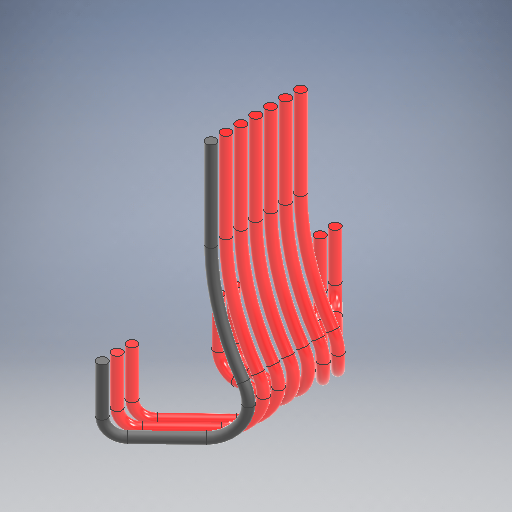
# Autodesk Inventor part: Charging Cables
Saved by Autodesk Inventor 2025 (Build 290162010, 162A)
## iProperties
Created: 2025-08-20
Part Number: Charging Cables
Material: Generic
Document SubType Name: Modeling
Designer: Glen Collingwood
Density: 1 g/cm^3
Appearance: Default
Author: Glen Collingwood
Autodesk Inventor part; units mm, degrees
sketch "Sketch1" plane through (0, 0, 0) normal (0, 1, 0) x (-1, 0, 0)
  circle A0 centre (0, 0) radius 0.85
  dimension "d0" = 1.7
  constraints: 1 centre point, 1 coincident
  measures "d0" diameter of A0
extrude "Extrusion1" add sketch "Sketch1" against normal blind 15
pattern_linear "Rectangular Pattern1" count 7 spacing 2.5 along (0, 0, 1) of "Extrusion1" first direction both ways yes
sketch "Sketch2" plane through (0, 0, 0) normal (0, 0, 1) x (1, 0, 0)
  line L0 (-14, -40) -> (22, -40) construction
  line L1 (-0.85, -15) -> (0.85, -15) projected
  arc A0 (0, -15) -> (5.3804, -32.1429) centre (30, -15) ccw
  arc A1 (6.2772, -35) -> (5.3804, -32.1429) centre (1.2772, -35) ccw
  line L2 (1.2772, -35) -> (6.2772, -35) construction
  point P0 (0, 0)
  dimension "d6" = 25
  dimension "d7" = 60
  dimension "d8" = 10
  constraints: 4 end point, 4 point on circle, 2 centre point, 2 horizontal, 2 midpoint, 2 tangent, 1 horizontal alignment
  measures "d6" distance between parallel lines of L0 L1
  measures "d7" diameter of A0
  measures "d8" diameter of A1
sketch "Sketch3" plane through (0, -15, 0) normal (0, -1, 0) x (1, 0, 0)
  circle A0 centre (0, 0) radius 0.85 projected
  circle A1 centre (0, -7.5) radius 0.85 projected
  circle A2 centre (0, -5) radius 0.85 projected
  circle A3 centre (0, -2.5) radius 0.85 projected
  circle A4 centre (0, 2.5) radius 0.85 projected
  circle A5 centre (0, 5) radius 0.85 projected
  circle A6 centre (0, 7.5) radius 0.85 projected
sweep "Sweep1" add profiles "Sketch3" path "Sketch2" path curves A0 A1 contours A0
pattern_linear "Rectangular Pattern2" count 7 spacing 2.5 along (0, 0, 1) of "Sweep1" first direction both ways yes
sketch "Sketch4" plane through (0, 0, 0) normal (0, 0, 1) x (1, 0, 0)
  arc A0 (5.4272, -35) -> (4.6829, -32.6286) centre (1.2772, -35) ccw projected
  arc A1 (-0.85, -15) -> (4.6829, -32.6286) centre (30, -15) ccw projected
  line L0 (-0.85, -15) -> (-0.85, 0) projected
  line L1 (-0.85, 0) -> (0.85, 0) projected
  line L2 (0.85, 0) -> (0.85, -15) projected
  arc A2 (0.85, -15) -> (6.078, -31.6571) centre (30, -15) ccw projected
  arc A3 (7.1272, -35) -> (6.078, -31.6571) centre (1.2772, -35) ccw projected
  line L3 (7.1272, -35) -> (5.4272, -35) projected
  line L4 (1.2772, -35) -> (1.2772, -40.85) construction
  arc A4 (1.2772, -40) -> (6.2772, -35) centre (1.2772, -35) ccw
  line L5 (1.2772, -40) -> (-3.2228, -40)
  arc A5 (-6.2228, -37) -> (-3.2228, -40) centre (-3.2228, -37) ccw
  line L6 (-3.2228, -37) -> (-6.2228, -37) construction
  point P0 (0, 0)
  dimension "d16" = 6
  dimension "d17" = 4.5
  constraints: 6 end point, 4 point on circle, 2 centre point, 2 horizontal, 2 midpoint, 1 coincident, 1 concentric, 1 point on line, 1 vertical, 1 vertical alignment
  measures "d16" diameter of A5
  measures "d17" distance of L5.start L5.end
sketch "Sketch5" plane through (6.2772, -35, 0) normal (0, -1, 0) x (1, 0, 0)
  circle A0 centre (0, 0) radius 0.85 projected
  circle A1 centre (0, -7.5) radius 0.85 projected
  circle A2 centre (0, -5) radius 0.85 projected
  circle A3 centre (0, -2.5) radius 0.85 projected
  circle A4 centre (0, 2.5) radius 0.85 projected
  circle A5 centre (0, 5) radius 0.85 projected
  circle A6 centre (0, 7.5) radius 0.85 projected
  point P0 (-6.2772, 0)
sweep "Sweep2" add profiles "Sketch5" path "Sketch4" path curves A5 L5 A4 contours A0
sketch "Sketch6" plane through (-6.2228, -37, 0) normal (0, 1, 0) x (1, 0, 0)
  circle A0 centre (0, 0) radius 0.85 projected
  point P0 (6.2228, 0)
  constraints: 1 other
extrude "Extrusion2" add sketch "Sketch6" along normal blind 8
pattern_linear "Rectangular Pattern4" count 2 spacing 2.5 along (0, 0, -1) of "Extrusion2", "Sweep2"
ref_plane "Work Plane2" through (-6.2228, -37, -2.5) normal (0, 0, -1) x (0, 1, 0)
ref_plane "Work Plane1" through (-6.2228, -37, -2.5) normal (1, 0, 0) x (0, 1, 0)
ref_plane "Work Plane4" through (-6.2228, -37, -17) normal (0, 0, -1) x (0, 1, 0)
ref_plane "Work Plane3" through (-6.2228, -37, -19.5) normal (0, 0, -1) x (0, 1, 0)
sketch "Sketch7" plane through (-6.2228, -29, 0) normal (0, 1, 0) x (1, 0, 0)
  line L0 (0, 26.094) -> (0, -14.1142) projected
  line L1 (-3.69, 17) -> (16.19, 17) projected
  line L2 (-3.69, 19.5) -> (16.19, 19.5) projected
  circle A0 centre (0, 19.5) radius 0.85
  circle A1 centre (0, 2.5) radius 0.85 projected
  circle A2 centre (0, 0) radius 0.85 projected
  circle A3 centre (0, 17) radius 0.85
  point P0 (6.2228, 0)
  dimension "d31" = 1.7
  dimension "d32" = 1.7
  constraints: 4 point on line, 2 centre point, 7 other
  measures "d31" diameter of A0
  measures "d32" diameter of A3
extrude "Extrusion3" add sketch "Sketch7" against normal blind 8 contours A0 L2 L0 | L0 L2 A0 | L2 A0 L0 | L0 A0 L2 | A3 L1 L0 | L0 L1 A3 | L1 A3 L0 | L0 A3 L1
pattern_linear "Rectangular Pattern5" count 2 spacing 34 along (0, 0, 1) of "Extrusion3"
ref_plane "Work Plane5" through (6.2772, -35, -5) normal (0.6925318, 0, -0.7213873) x (0, -1, 0)
sketch "Sketch8" plane through (6.2772, -35, -5) normal (0.6925318, 0, -0.7213873) x (0, -1, 0)
  line L0 (-6, 18.1777) -> (2, 18.1777) projected
  line L1 (2, 18.1777) -> (2, 16.4777) projected
  line L2 (2, 16.4777) -> (-6, 16.4777) projected
  line L3 (-6, 16.4777) -> (-6, 18.1777) projected
  line L4 (0, 0.85) -> (0, -0.85) projected
  line L5 (5.85, 5.1218) -> (5.85, 1.8756) construction
  line L6 (4.15, 5.1218) -> (4.15, 1.8756) construction
  ellipse E0 centre (5, 3.3905) end of major axis (5.85, 3.3905) minor radius 0.5887 construction
  line L7 (4.15, 3.3905) -> (5.85, 3.3905) construction
  line L8 (0, -0.85) -> (0, 0.85) projected
  line L9 (0, 0) -> (0, 0)
  line L10 (5, 5) -> (5, 14.3277)
  line L11 (2, 17.3277) -> (2, 17.3277)
  line L12 (-43.17, 17.3277) -> (14.02, 17.3277) construction
  arc A0 (5, 14.3277) -> (2, 17.3277) centre (2, 14.3277) ccw
  arc A1 (0, 0) -> (5, 5) centre (0, 5) ccw
  point P0 (-35, 1.0656)
  point P1 (5, 17.3277)
  dimension "d38" = 3
  dimension "d39" = 5
  constraints: 8 end point, 5 point on line, 4 point on circle, 4 tangent, 3 midpoint, 2 centre point, 1 collinear, 1 horizontal, 1 perpendicular, 7 other
  measures "d38" radius of A0
  measures "d39" radius of A1
sketch "Sketch9" plane through (6.2772, -35, -5) normal (0, -1, 0) x (1, 0, 0)
  circle A0 centre (-12.5, -12) radius 0.85 projected
  circle A1 centre (-12.5, -14.5) radius 0.85 projected
  circle A2 centre (0, 12.5) radius 0.85 projected
  circle A3 centre (0, 10) radius 0.85 projected
  circle A4 centre (0, 7.5) radius 0.85 projected
  circle A5 centre (-12.5, 2.5) radius 0.85 projected
  circle A6 centre (0, 2.5) radius 0.85 projected
  circle A7 centre (0, 0) radius 0.85 projected
  circle A8 centre (0, -2.5) radius 0.85 projected
  circle A9 centre (-12.5, 5) radius 0.85 projected
  circle A10 centre (0, 5) radius 0.85 projected
  circle A11 centre (-12.5, 19.5) radius 0.85 projected
  circle A12 centre (-12.5, 22) radius 0.85 projected
  point P0 (-6.2772, 5)
sweep "Sweep3" add profiles "Sketch9" path "Sketch8" path curves L9 A1 L10 A0 L11 contours A7
ref_plane "Work Plane6" through (6.2772, -35, -7.5) normal (0.6925318, 0, -0.7213873) x (0, -1, 0)
sketch "Sketch10" plane through (6.2772, -35, -7.5) normal (0.6925318, 0, -0.7213873) x (0, -1, 0)
  line L0 (0, 0.85) -> (0, -0.85) projected
  line L1 (-6, 18.1777) -> (2, 18.1777) projected
  line L2 (2, 18.1777) -> (2, 16.4777) projected
  line L3 (2, 16.4777) -> (-6, 16.4777) projected
  line L4 (-6, 16.4777) -> (-6, 18.1777) projected
  line L5 (4.15, 3.2687) -> (4.15, 12.5964) construction
  line L6 (5.85, 3.2687) -> (5.85, 12.5964) construction
  line L7 (4.15, 7.9325) -> (5.85, 7.9325) construction
  line L8 (0, 0) -> (0, 0)
  line L9 (5, 5) -> (5, 14.3277)
  line L10 (2, 17.3277) -> (2, 17.3277)
  line L11 (-43.17, 17.3277) -> (14.02, 17.3277) construction
  arc A0 (0, 0) -> (5, 5) centre (0, 5) ccw
  arc A1 (5, 14.3277) -> (2, 17.3277) centre (2, 14.3277) ccw
  point P0 (-35, -0.6657)
  point P1 (5, 17.3277)
  point P2 (5, 7.9325)
  dimension "d42" = 5
  dimension "d43" = 3
  constraints: 8 end point, 5 midpoint, 4 point on circle, 4 tangent, 3 point on line, 2 centre point, 1 collinear, 1 parallel, 1 perpendicular, 3 other
  measures "d42" radius of A0
  measures "d43" radius of A1
sketch "Sketch11" plane through (6.2772, -35, -7.5) normal (0, -1, 0) x (1, 0, 0)
  circle A0 centre (-12.5, 24.5) radius 0.85 projected
  circle A1 centre (-12.5, 22) radius 0.85 projected
  circle A2 centre (-12.5, 7.5) radius 0.85 projected
  circle A3 centre (0, 7.5) radius 0.85 projected
  circle A4 centre (0, 0) radius 0.85 projected
  circle A5 centre (-12.5, 5) radius 0.85 projected
  circle A6 centre (0, 5) radius 0.85 projected
  circle A7 centre (0, 10) radius 0.85 projected
  circle A8 centre (0, 12.5) radius 0.85 projected
  circle A9 centre (0, 15) radius 0.85 projected
  circle A10 centre (-12.5, -12) radius 0.85 projected
  circle A11 centre (0, 2.5) radius 0.85 projected
  circle A12 centre (-12.5, -9.5) radius 0.85 projected
  point P0 (-6.2772, 7.5)
sweep "Sweep4" add profiles "Sketch11" path "Sketch10" path curves L8 A0 L9 A1 L10 contours A4
ref_plane "Work Plane7" through (-6.2228, -37, -1.25) normal (0, 0, -1) x (0, 1, 0)
mirror "Mirror2" about plane through (-6.2228, -37, -1.25) normal (0, 0, -1) of "Sweep3", "Sweep4"
sketch "Sketch12" plane through (-6.2228, -29, 17) normal (0, 1, 0) x (1, 0, 0)
  circle A0 centre (0, 0) radius 0.85 projected
  line L0 (0, 0) -> (0, -2.5)
  circle A1 centre (0, -2.5) radius 0.85
  point P0 (6.2228, 17)
  dimension "d47" = 2.5
  dimension "d48" = 1.7
  constraints: 2 end point, 1 centre point, 1 coincident, 1 vertical
  measures "d47" distance of L0.start L0.end
  measures "d48" diameter of A1
extrude "Extrusion4" add sketch "Sketch12" against normal blind 8 contours A1
ref_plane "Work Plane8" through (-6.2228, -29, 19.5) normal (0.6925318, 0, 0.7213873) x (0, -1, 0)
sketch "Sketch13" plane through (-6.2228, -29, 19.5) normal (0.6925318, 0, 0.7213873) x (0, -1, 0)
  line L0 (6, 18.1777) -> (6, 16.4777) projected
  line L1 (0, 0.85) -> (8, 0.85) projected
  line L2 (8, 0.85) -> (8, -0.85) projected
  line L3 (8, -0.85) -> (0, -0.85) projected
  line L4 (0, -0.85) -> (0, 0.85) projected
  line L5 (11.85, 4.7313) -> (11.85, 14.0591) construction
  line L6 (10.15, 4.7313) -> (10.15, 14.0591) construction
  line L7 (10.15, 6.4627) -> (10.15, 15.7904) construction
  line L8 (10.15, 9.3952) -> (11.85, 9.3952) construction
  line L9 (8, 0) -> (8, 0)
  line L10 (11, 3) -> (11, 12.3277)
  line L11 (6, 17.3277) -> (6, 17.3277)
  line L12 (-37.2071, 17.3277) -> (20.2426, 17.3277) construction
  arc A0 (8, 0) -> (11, 3) centre (8, 3) ccw
  arc A1 (11, 12.3277) -> (6, 17.3277) centre (6, 12.3277) ccw
  point P0 (-29, 17.9934)
  point P1 (11, 17.3277)
  point P2 (11, 9.3952)
  dimension "d51" = 3
  dimension "d52" = 5
  constraints: 8 end point, 5 midpoint, 5 point on line, 4 point on circle, 4 tangent, 2 centre point, 2 perpendicular, 1 collinear, 1 horizontal, 3 other
  measures "d51" radius of A0
  measures "d52" radius of A1
sketch "Sketch14" plane through (-6.2228, -37, 19.5) normal (0, -1, 0) x (1, 0, 0)
  circle A0 centre (0, -36.5) radius 0.85 projected
  circle A1 centre (0, -2.5) radius 0.85 projected
  circle A2 centre (0, -5) radius 0.85 projected
  circle A3 centre (0, -22) radius 0.85 projected
  circle A4 centre (0, -39) radius 0.85 projected
  circle A5 centre (0, -19.5) radius 0.85 projected
  circle A6 centre (0, 0) radius 0.85 projected
  point P0 (6.2228, -19.5)
  constraints: 6 other
sweep "Sweep5" add profiles "Sketch14" path "Sketch13" path curves L9 A0 L10 A1 L11 contours A6
body "Solid1"
